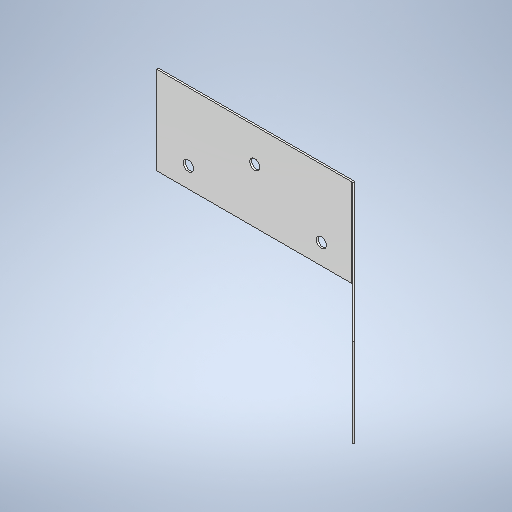
# Autodesk Inventor part: DMF-1002 Drum Sheet
Saved by Autodesk Inventor 2026.2 (Build 302298000, 298)
## iProperties
Created: 2024-04-28
Part Number: DMF-1002 Drum Sheet
Material: Stainless Steel AISI 304
Document SubType Name: Sheet Metal
Designer: admin
Stock Number: DMF-1002
Density: 8 g/cm^3
Flat Pattern Width: 42.6948 cm
Flat Pattern Length: 9.6 cm
Flat Pattern Area: 409.87 cm^2
Sheet Metal Rule: Default
Sheet Metal Width: 426,948 mm
Sheet Metal Length: 96,000 mm
Sheet Metal Area: 40987,031 mm^2
Appearance: Chrome - Satin
Mass: 448.229 g
Surface Area: 394.889 cm^2
Volume: 56.0286 cm^3
Author: pokla
Autodesk Inventor part; units mm, degrees
ref_plane "YZ Plane" through (0, 0, 0) normal (1, 0, 0) x (0, 1, 0)
ref_plane "XZ Plane" through (0, 0, 0) normal (0, 1, 0) x (-1, 0, 0)
sketch "Sketch15" plane through (0, 0, 0) normal (0, 0, 1) x (1, 0, 0)
  line L0 (-107, 48) -> (107, 48)
  line L1 (107, 48) -> (107, -48)
  line L2 (107, -48) -> (-107, -48)
  line L3 (-107, -48) -> (-107, 48)
  line L4 (-107, 48) -> (107, -48) construction
  line L5 (107, 48) -> (-107, -48) construction
  circle A0 centre (0, 11.5) radius 5.5
  circle A1 centre (72.5, -26) radius 5.5
  circle A2 centre (-72.5, -26) radius 5.5
  line L6 (0, 0) -> (0, -48) construction
  dimension "d173" = 214
  dimension "d174" = 96
  dimension "d176" = 11
  dimension "d177" = 11
  dimension "d178" = 11.5
  dimension "d179" = 26
  dimension "d180" = 145
  measures "d173" distance of L1.end L2.end
  measures "d174" distance of L0.end L1.end
  measures "d176" diameter of A0
  measures "d177" diameter of A1
  measures "d178" distance of L6.start A0.centre
  measures "d179" vertical distance of L6.start A1.centre
  measures "d180" distance of A2.centre A1.centre
extrude "Plate10" add sketch "Sketch15" along normal blind 2 contours L0 L1 L2 L3 | A0 | A1 | A2
sketch "Sketch16" plane through (105.5858, 48, 1.4142) normal (0.7071068, 0, -0.7071068) x (0, 1, 0)
  line L0 (-96, 0) -> (0, 0)
  line L1 (0, 0) -> (0, 214)
  line L2 (0, 214) -> (-96, 214)
  line L3 (-96, 214) -> (-96, 0)
  constraints: 6 end point, 1 horizontal, 1 perpendicular, 1 vertical
edge flange "Flange8" height 214 angle 45 thickness 2 bend radius 2 thickness toward (0.7071068, 0, -0.7071068) relief tear relief width 2 relief depth 1 edges at (107, 0, 2) wall of the first edge with corners at (105.5858, -48, 1.4142) (105.5858, 48, 1.4142) (256.9066, 48, 152.7351) (256.9066, -48, 152.7351)
bend "Bend10"
corner "Corner10"
ref_plane "Work Plane1" through (106.1716, 0, 2) normal (0.9238795, 0, 0.3826834) x (0, 1, 0)
sketch "Sketch17" plane through (0, 0, 0) normal (0, 0, -1) x (-1, 0, 0)
  circle A0 centre (72.5, -26) radius 5.5
  circle A1 centre (0, 11.5) radius 5.5
  circle A2 centre (-72.5, -26) radius 5.5
  line L0 (72.5, -26) -> (-72.5, -26) construction
  line L1 (0, -26) -> (0, 11.5) construction
  point P0 (0, 0)
  dimension "d191" = 11
  dimension "d193" = 145
  dimension "d194" = 26
  dimension "d197" = 11.5
  dimension "d198" = 0
  constraints: 4 end point, 3 centre point, 2 equal radius, 1 coincident, 1 horizontal, 1 midpoint, 1 perpendicular
  measures "d191" diameter of A1
  measures "d193" distance of L0.end L0.start
  measures "d194" vertical distance of point (0, 0) L0.end
  measures "d197" distance of A1.centre point (0, 0)
  measures "d198" distance from line of point (0, 0) L1
extrude "Cut1" cut sketch "Sketch17" against normal blind 2
mirror "Mirror1" about plane through (106.1716, 0, 2) normal (0.9238795, 0, 0.3826834) of "Cut1"
equation "\"BendRadius\" = Thickness"
equation "\"BendReliefWidth\" = Thickness"
equation "\"BendReliefDepth\" = 0.5 * Thickness"
equation "\"CornerReliefSize\" = 4 * Thickness"
equation "\"MinimumRemnant\" = 2 * Thickness"
equation "\"TransitionRadius\" = BendRadius"
equation "\"JacobiRadiusSize\" = BendRadius"
equation "\"GapSize\" = Thickness"
equation "\"Thickness\" = 2"
body "Solid3"
